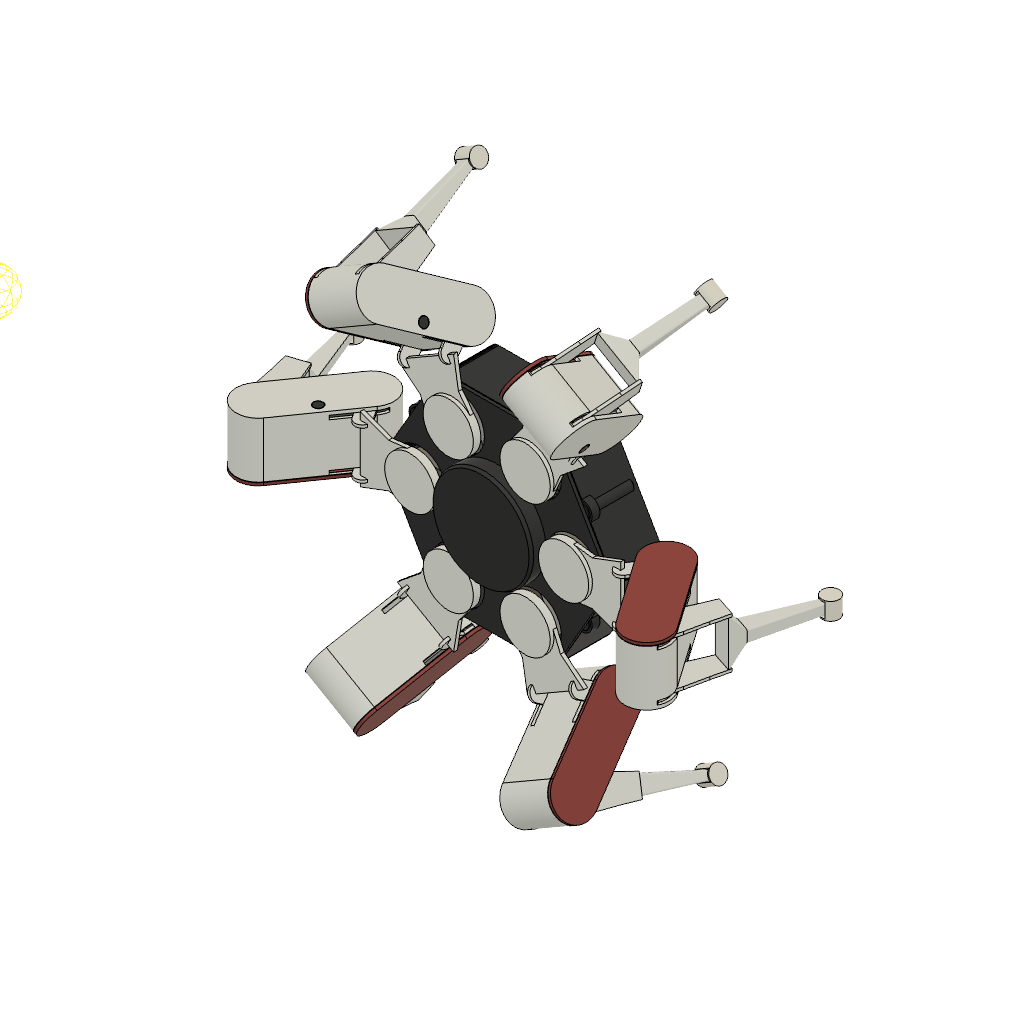
final-concept (Autodesk Fusion 360 design; units mm, degrees)
part number: 2026-10-13-02-30-10-488
part number: 2026-10-13-02-30-11-030
part number: 2026-10-13-02-30-12-968
part number: 2026-10-13-02-30-14-273
part number: 2026-10-13-02-30-15-877
part number: 2026-10-13-02-30-17-179
part number: 2026-10-13-02-30-18-648
part number: 2026-10-13-02-30-19-201
part number: 2026-10-13-02-30-20-901
part number: 2026-10-13-02-30-21-364
part number: 2026-10-13-02-30-21-593
part number: 2026-10-13-02-30-21-831
part number: 2026-10-13-02-30-33-109
part number: 2026-10-13-02-30-33-523
part number: 2026-10-13-02-30-34-018
part number: 2026-10-13-02-30-34-370
part number: 2026-10-13-02-30-34-939
part number: 2026-10-13-02-30-35-478
part number: 2026-10-13-02-30-36-031
part number: 2026-10-13-02-30-36-586
part number: 2026-10-13-02-30-37-150
part number: 2026-10-13-02-30-37-730
part number: 2026-10-13-02-30-38-365
part number: 2026-10-13-02-30-39-006
part number: 2026-10-13-02-30-39-649
part number: 2026-10-13-02-30-40-309
part number: 2026-10-13-02-30-40-984
Autodesk Fusion 360 part; units mm, degrees
(part 1 of 3)
ref_plane "WorkPlane1" through (0, 0, -32) normal (0, 0, 1) x (1, 0, 0) in component "CORE | CoreTub"
sketch "Continuous structural body" plane through (0, 0, -32) normal (0, 0, 1) x (1, 0, 0) in component "CORE | CoreTub"
  line L0 (71.1962, -3) -> (71.5433, -2.2961)
  line L1 (71.5433, -2.2961) -> (71.7956, -1.5529)
  line L2 (71.7956, -1.5529) -> (71.9487, -0.7832)
  line L3 (71.9487, -0.7832) -> (72, 0)
  line L4 (72, 0) -> (71.9487, 0.7832)
  line L5 (71.9487, 0.7832) -> (71.7956, 1.5529)
  line L6 (71.7956, 1.5529) -> (71.5433, 2.2961)
  line L7 (71.5433, 2.2961) -> (71.1962, 3)
  line L8 (71.1962, 3) -> (38.1962, 60.1577)
  line L9 (38.1962, 60.1577) -> (37.7601, 60.8102)
  line L10 (37.7601, 60.8102) -> (37.2426, 61.4003)
  line L11 (37.2426, 61.4003) -> (36.6526, 61.9178)
  line L12 (36.6526, 61.9178) -> (36, 62.3538)
  line L13 (36, 62.3538) -> (35.2961, 62.701)
  line L14 (35.2961, 62.701) -> (34.5529, 62.9532)
  line L15 (34.5529, 62.9532) -> (33.7832, 63.1063)
  line L16 (33.7832, 63.1063) -> (33, 63.1577)
  line L17 (33, 63.1577) -> (-33, 63.1577)
  line L18 (-33, 63.1577) -> (-33.7832, 63.1063)
  line L19 (-33.7832, 63.1063) -> (-34.5529, 62.9532)
  line L20 (-34.5529, 62.9532) -> (-35.2961, 62.701)
  line L21 (-35.2961, 62.701) -> (-36, 62.3538)
  line L22 (-36, 62.3538) -> (-36.6526, 61.9178)
  line L23 (-36.6526, 61.9178) -> (-37.2426, 61.4003)
  line L24 (-37.2426, 61.4003) -> (-37.7601, 60.8102)
  line L25 (-37.7601, 60.8102) -> (-38.1962, 60.1577)
  line L26 (-38.1962, 60.1577) -> (-71.1962, 3)
  line L27 (-71.1962, 3) -> (-71.5433, 2.2961)
  line L28 (-71.5433, 2.2961) -> (-71.7956, 1.5529)
  line L29 (-71.7956, 1.5529) -> (-71.9487, 0.7832)
  line L30 (-71.9487, 0.7832) -> (-72, 0)
  line L31 (-72, 0) -> (-71.9487, -0.7832)
  line L32 (-71.9487, -0.7832) -> (-71.7956, -1.5529)
  line L33 (-71.7956, -1.5529) -> (-71.5433, -2.2961)
  line L34 (-71.5433, -2.2961) -> (-71.1962, -3)
  line L35 (-71.1962, -3) -> (-38.1962, -60.1577)
  line L36 (-38.1962, -60.1577) -> (-37.7601, -60.8102)
  line L37 (-37.7601, -60.8102) -> (-37.2426, -61.4003)
  line L38 (-37.2426, -61.4003) -> (-36.6526, -61.9178)
  line L39 (-36.6526, -61.9178) -> (-36, -62.3538)
  line L40 (-36, -62.3538) -> (-35.2961, -62.701)
  line L41 (-35.2961, -62.701) -> (-34.5529, -62.9532)
  line L42 (-34.5529, -62.9532) -> (-33.7832, -63.1063)
  line L43 (-33.7832, -63.1063) -> (-33, -63.1577)
  line L44 (-33, -63.1577) -> (33, -63.1577)
  line L45 (33, -63.1577) -> (33.7832, -63.1063)
  line L46 (33.7832, -63.1063) -> (34.5529, -62.9532)
  line L47 (34.5529, -62.9532) -> (35.2961, -62.701)
  line L48 (35.2961, -62.701) -> (36, -62.3538)
  line L49 (36, -62.3538) -> (36.6526, -61.9178)
  line L50 (36.6526, -61.9178) -> (37.2426, -61.4003)
  line L51 (37.2426, -61.4003) -> (37.7601, -60.8102)
  line L52 (37.7601, -60.8102) -> (38.1962, -60.1577)
  line L53 (38.1962, -60.1577) -> (71.1962, -3)
extrude "Continuous structural body (1)" add sketch "Continuous structural body" along normal blind 32 makes body 1 in component "CORE | CoreTub"
ref_plane "WorkPlane2" through (0, 0, -29) normal (0, 0, 1) x (1, 0, 0) in component "CORE | CoreTub"
sketch "Hollow core with 3mm floor and 1.8mm walls" plane through (0, 0, -29) normal (0, 0, 1) x (1, 0, 0) in component "CORE | CoreTub"
  line L0 (69.6373, -2.1) -> (69.8803, -1.6073)
  line L1 (69.8803, -1.6073) -> (70.0569, -1.087)
  line L2 (70.0569, -1.087) -> (70.1641, -0.5482)
  line L3 (70.1641, -0.5482) -> (70.2, 0)
  line L4 (70.2, 0) -> (70.1641, 0.5482)
  line L5 (70.1641, 0.5482) -> (70.0569, 1.087)
  line L6 (70.0569, 1.087) -> (69.8803, 1.6073)
  line L7 (69.8803, 1.6073) -> (69.6373, 2.1)
  line L8 (69.6373, 2.1) -> (36.6373, 59.2577)
  line L9 (36.6373, 59.2577) -> (36.3321, 59.7145)
  line L10 (36.3321, 59.7145) -> (35.9698, 60.1275)
  line L11 (35.9698, 60.1275) -> (35.5568, 60.4898)
  line L12 (35.5568, 60.4898) -> (35.1, 60.795)
  line L13 (35.1, 60.795) -> (34.6073, 61.038)
  line L14 (34.6073, 61.038) -> (34.087, 61.2146)
  line L15 (34.087, 61.2146) -> (33.5482, 61.3217)
  line L16 (33.5482, 61.3217) -> (33, 61.3577)
  line L17 (33, 61.3577) -> (-33, 61.3577)
  line L18 (-33, 61.3577) -> (-33.5482, 61.3217)
  line L19 (-33.5482, 61.3217) -> (-34.087, 61.2146)
  line L20 (-34.087, 61.2146) -> (-34.6073, 61.038)
  line L21 (-34.6073, 61.038) -> (-35.1, 60.795)
  line L22 (-35.1, 60.795) -> (-35.5568, 60.4898)
  line L23 (-35.5568, 60.4898) -> (-35.9698, 60.1275)
  line L24 (-35.9698, 60.1275) -> (-36.3321, 59.7145)
  line L25 (-36.3321, 59.7145) -> (-36.6373, 59.2577)
  line L26 (-36.6373, 59.2577) -> (-69.6373, 2.1)
  line L27 (-69.6373, 2.1) -> (-69.8803, 1.6073)
  line L28 (-69.8803, 1.6073) -> (-70.0569, 1.087)
  line L29 (-70.0569, 1.087) -> (-70.1641, 0.5482)
  line L30 (-70.1641, 0.5482) -> (-70.2, 0)
  line L31 (-70.2, 0) -> (-70.1641, -0.5482)
  line L32 (-70.1641, -0.5482) -> (-70.0569, -1.087)
  line L33 (-70.0569, -1.087) -> (-69.8803, -1.6073)
  line L34 (-69.8803, -1.6073) -> (-69.6373, -2.1)
  line L35 (-69.6373, -2.1) -> (-36.6373, -59.2577)
  line L36 (-36.6373, -59.2577) -> (-36.3321, -59.7145)
  line L37 (-36.3321, -59.7145) -> (-35.9698, -60.1275)
  line L38 (-35.9698, -60.1275) -> (-35.5568, -60.4898)
  line L39 (-35.5568, -60.4898) -> (-35.1, -60.795)
  line L40 (-35.1, -60.795) -> (-34.6073, -61.038)
  line L41 (-34.6073, -61.038) -> (-34.087, -61.2146)
  line L42 (-34.087, -61.2146) -> (-33.5482, -61.3217)
  line L43 (-33.5482, -61.3217) -> (-33, -61.3577)
  line L44 (-33, -61.3577) -> (33, -61.3577)
  line L45 (33, -61.3577) -> (33.5482, -61.3217)
  line L46 (33.5482, -61.3217) -> (34.087, -61.2146)
  line L47 (34.087, -61.2146) -> (34.6073, -61.038)
  line L48 (34.6073, -61.038) -> (35.1, -60.795)
  line L49 (35.1, -60.795) -> (35.5568, -60.4898)
  line L50 (35.5568, -60.4898) -> (35.9698, -60.1275)
  line L51 (35.9698, -60.1275) -> (36.3321, -59.7145)
  line L52 (36.3321, -59.7145) -> (36.6373, -59.2577)
  line L53 (36.6373, -59.2577) -> (69.6373, -2.1)
extrude "Hollow core with 3mm floor and 1.8mm walls (1)" cut sketch "Hollow core with 3mm floor and 1.8mm walls" along normal blind 29 bodies 1 in component "CORE | CoreTub"
ref_plane "WorkPlane3" through (0, 0, -29) normal (0, 0, 1) x (1, 0, 0) in component "CORE | CoreTub"
sketch "Integral concealed lid screw column" plane through (0, 0, -29) normal (0, 0, 1) x (1, 0, 0) in component "CORE | CoreTub"
  circle A0 centre (51.9615, 30) radius 4.2
extrude "Integral concealed lid screw column (1)" add sketch "Integral concealed lid screw column" along normal blind 29 bodies 1 in component "CORE | CoreTub"
ref_plane "WorkPlane4" through (0, 0, -32) normal (0, 0, 1) x (1, 0, 0) in component "CORE | CoreTub"
sketch "Underside M3 clearance shaft" plane through (0, 0, -32) normal (0, 0, 1) x (1, 0, 0) in component "CORE | CoreTub"
  circle A0 centre (51.9615, 30) radius 1.7
extrude "Underside M3 clearance shaft (1)" cut sketch "Underside M3 clearance shaft" along normal blind 32 bodies 1 in component "CORE | CoreTub"
ref_plane "WorkPlane5" through (0, 0, -32) normal (0, 0, 1) x (1, 0, 0) in component "CORE | CoreTub"
sketch "Recessed underside screw head" plane through (0, 0, -32) normal (0, 0, 1) x (1, 0, 0) in component "CORE | CoreTub"
  circle A0 centre (51.9615, 30) radius 3.1
extrude "Recessed underside screw head (1)" cut sketch "Recessed underside screw head" along normal blind 2 bodies 1 in component "CORE | CoreTub"
ref_plane "WorkPlane6" through (0, 0, -5) normal (0, 0, 1) x (1, 0, 0) in component "CORE | CoreTub"
sketch "Integral wide insert seating collar" plane through (0, 0, -5) normal (0, 0, 1) x (1, 0, 0) in component "CORE | CoreTub"
  circle A0 centre (51.9615, 30) radius 6.5
extrude "Integral wide insert seating collar (1)" add sketch "Integral wide insert seating collar" along normal blind 5 bodies 1 in component "CORE | CoreTub"
ref_plane "WorkPlane7" through (0, 0, -5) normal (0, 0, 1) x (1, 0, 0) in component "CORE | CoreTub"
sketch "Keep screw shaft open through widened collar" plane through (0, 0, -5) normal (0, 0, 1) x (1, 0, 0) in component "CORE | CoreTub"
  circle A0 centre (51.9615, 30) radius 1.7
extrude "Keep screw shaft open through widened collar (1)" cut sketch "Keep screw shaft open through widened collar" along normal blind 5 bodies 1 in component "CORE | CoreTub"
ref_plane "WorkPlane8" through (0, 0, -4) normal (0, 0, 1) x (1, 0, 0) in component "CORE | CoreTub"
sketch "Lid boss receiving pocket with radial clearance" plane through (0, 0, -4) normal (0, 0, 1) x (1, 0, 0) in component "CORE | CoreTub"
  circle A0 centre (51.9615, 30) radius 5.3
extrude "Lid boss receiving pocket with radial clearance (1)" cut sketch "Lid boss receiving pocket with radial clearance" along normal blind 4 bodies 1 in component "CORE | CoreTub"
ref_plane "WorkPlane9" through (0, 0, -29) normal (0, 0, 1) x (1, 0, 0) in component "CORE | CoreTub"
sketch "Integral concealed lid screw column (1)" plane through (0, 0, -29) normal (0, 0, 1) x (1, 0, 0) in component "CORE | CoreTub"
  circle A0 centre (-51.9615, 30) radius 4.2
extrude "Integral concealed lid screw column (2)" add sketch "Integral concealed lid screw column (1)" along normal blind 29 bodies 1 in component "CORE | CoreTub"
ref_plane "WorkPlane10" through (0, 0, -32) normal (0, 0, 1) x (1, 0, 0) in component "CORE | CoreTub"
sketch "Underside M3 clearance shaft (1)" plane through (0, 0, -32) normal (0, 0, 1) x (1, 0, 0) in component "CORE | CoreTub"
  circle A0 centre (-51.9615, 30) radius 1.7
extrude "Underside M3 clearance shaft (2)" cut sketch "Underside M3 clearance shaft (1)" along normal blind 32 bodies 1 in component "CORE | CoreTub"
ref_plane "WorkPlane11" through (0, 0, -32) normal (0, 0, 1) x (1, 0, 0) in component "CORE | CoreTub"
sketch "Recessed underside screw head (1)" plane through (0, 0, -32) normal (0, 0, 1) x (1, 0, 0) in component "CORE | CoreTub"
  circle A0 centre (-51.9615, 30) radius 3.1
extrude "Recessed underside screw head (2)" cut sketch "Recessed underside screw head (1)" along normal blind 2 bodies 1 in component "CORE | CoreTub"
ref_plane "WorkPlane12" through (0, 0, -5) normal (0, 0, 1) x (1, 0, 0) in component "CORE | CoreTub"
sketch "Integral wide insert seating collar (1)" plane through (0, 0, -5) normal (0, 0, 1) x (1, 0, 0) in component "CORE | CoreTub"
  circle A0 centre (-51.9615, 30) radius 6.5
extrude "Integral wide insert seating collar (2)" add sketch "Integral wide insert seating collar (1)" along normal blind 5 bodies 1 in component "CORE | CoreTub"
ref_plane "WorkPlane13" through (0, 0, -5) normal (0, 0, 1) x (1, 0, 0) in component "CORE | CoreTub"
sketch "Keep screw shaft open through widened collar (1)" plane through (0, 0, -5) normal (0, 0, 1) x (1, 0, 0) in component "CORE | CoreTub"
  circle A0 centre (-51.9615, 30) radius 1.7
extrude "Keep screw shaft open through widened collar (2)" cut sketch "Keep screw shaft open through widened collar (1)" along normal blind 5 bodies 1 in component "CORE | CoreTub"
ref_plane "WorkPlane14" through (0, 0, -4) normal (0, 0, 1) x (1, 0, 0) in component "CORE | CoreTub"
sketch "Lid boss receiving pocket with radial clearance (1)" plane through (0, 0, -4) normal (0, 0, 1) x (1, 0, 0) in component "CORE | CoreTub"
  circle A0 centre (-51.9615, 30) radius 5.3
extrude "Lid boss receiving pocket with radial clearance (2)" cut sketch "Lid boss receiving pocket with radial clearance (1)" along normal blind 4 bodies 1 in component "CORE | CoreTub"
ref_plane "WorkPlane15" through (0, 0, -29) normal (0, 0, 1) x (1, 0, 0) in component "CORE | CoreTub"
sketch "Integral concealed lid screw column (2)" plane through (0, 0, -29) normal (0, 0, 1) x (1, 0, 0) in component "CORE | CoreTub"
  circle A0 centre (-51.9615, -30) radius 4.2
extrude "Integral concealed lid screw column (3)" add sketch "Integral concealed lid screw column (2)" along normal blind 29 bodies 1 in component "CORE | CoreTub"
ref_plane "WorkPlane16" through (0, 0, -32) normal (0, 0, 1) x (1, 0, 0) in component "CORE | CoreTub"
sketch "Underside M3 clearance shaft (2)" plane through (0, 0, -32) normal (0, 0, 1) x (1, 0, 0) in component "CORE | CoreTub"
  circle A0 centre (-51.9615, -30) radius 1.7
extrude "Underside M3 clearance shaft (3)" cut sketch "Underside M3 clearance shaft (2)" along normal blind 32 bodies 1 in component "CORE | CoreTub"
ref_plane "WorkPlane17" through (0, 0, -32) normal (0, 0, 1) x (1, 0, 0) in component "CORE | CoreTub"
sketch "Recessed underside screw head (2)" plane through (0, 0, -32) normal (0, 0, 1) x (1, 0, 0) in component "CORE | CoreTub"
  circle A0 centre (-51.9615, -30) radius 3.1
extrude "Recessed underside screw head (3)" cut sketch "Recessed underside screw head (2)" along normal blind 2 bodies 1 in component "CORE | CoreTub"
ref_plane "WorkPlane18" through (0, 0, -5) normal (0, 0, 1) x (1, 0, 0) in component "CORE | CoreTub"
sketch "Integral wide insert seating collar (2)" plane through (0, 0, -5) normal (0, 0, 1) x (1, 0, 0) in component "CORE | CoreTub"
  circle A0 centre (-51.9615, -30) radius 6.5
extrude "Integral wide insert seating collar (3)" add sketch "Integral wide insert seating collar (2)" along normal blind 5 bodies 1 in component "CORE | CoreTub"
ref_plane "WorkPlane19" through (0, 0, -5) normal (0, 0, 1) x (1, 0, 0) in component "CORE | CoreTub"
sketch "Keep screw shaft open through widened collar (2)" plane through (0, 0, -5) normal (0, 0, 1) x (1, 0, 0) in component "CORE | CoreTub"
  circle A0 centre (-51.9615, -30) radius 1.7
extrude "Keep screw shaft open through widened collar (3)" cut sketch "Keep screw shaft open through widened collar (2)" along normal blind 5 bodies 1 in component "CORE | CoreTub"
ref_plane "WorkPlane20" through (0, 0, -4) normal (0, 0, 1) x (1, 0, 0) in component "CORE | CoreTub"
sketch "Lid boss receiving pocket with radial clearance (2)" plane through (0, 0, -4) normal (0, 0, 1) x (1, 0, 0) in component "CORE | CoreTub"
  circle A0 centre (-51.9615, -30) radius 5.3
extrude "Lid boss receiving pocket with radial clearance (3)" cut sketch "Lid boss receiving pocket with radial clearance (2)" along normal blind 4 bodies 1 in component "CORE | CoreTub"
ref_plane "WorkPlane21" through (0, 0, -29) normal (0, 0, 1) x (1, 0, 0) in component "CORE | CoreTub"
sketch "Integral concealed lid screw column (3)" plane through (0, 0, -29) normal (0, 0, 1) x (1, 0, 0) in component "CORE | CoreTub"
  circle A0 centre (51.9615, -30) radius 4.2
extrude "Integral concealed lid screw column (4)" add sketch "Integral concealed lid screw column (3)" along normal blind 29 bodies 1 in component "CORE | CoreTub"
ref_plane "WorkPlane22" through (0, 0, -32) normal (0, 0, 1) x (1, 0, 0) in component "CORE | CoreTub"
sketch "Underside M3 clearance shaft (3)" plane through (0, 0, -32) normal (0, 0, 1) x (1, 0, 0) in component "CORE | CoreTub"
  circle A0 centre (51.9615, -30) radius 1.7
extrude "Underside M3 clearance shaft (4)" cut sketch "Underside M3 clearance shaft (3)" along normal blind 32 bodies 1 in component "CORE | CoreTub"
ref_plane "WorkPlane23" through (0, 0, -32) normal (0, 0, 1) x (1, 0, 0) in component "CORE | CoreTub"
sketch "Recessed underside screw head (3)" plane through (0, 0, -32) normal (0, 0, 1) x (1, 0, 0) in component "CORE | CoreTub"
  circle A0 centre (51.9615, -30) radius 3.1
extrude "Recessed underside screw head (4)" cut sketch "Recessed underside screw head (3)" along normal blind 2 bodies 1 in component "CORE | CoreTub"
ref_plane "WorkPlane24" through (0, 0, -5) normal (0, 0, 1) x (1, 0, 0) in component "CORE | CoreTub"
sketch "Integral wide insert seating collar (3)" plane through (0, 0, -5) normal (0, 0, 1) x (1, 0, 0) in component "CORE | CoreTub"
  circle A0 centre (51.9615, -30) radius 6.5
extrude "Integral wide insert seating collar (4)" add sketch "Integral wide insert seating collar (3)" along normal blind 5 bodies 1 in component "CORE | CoreTub"
ref_plane "WorkPlane25" through (0, 0, -5) normal (0, 0, 1) x (1, 0, 0) in component "CORE | CoreTub"
sketch "Keep screw shaft open through widened collar (3)" plane through (0, 0, -5) normal (0, 0, 1) x (1, 0, 0) in component "CORE | CoreTub"
  circle A0 centre (51.9615, -30) radius 1.7
extrude "Keep screw shaft open through widened collar (4)" cut sketch "Keep screw shaft open through widened collar (3)" along normal blind 5 bodies 1 in component "CORE | CoreTub"
ref_plane "WorkPlane26" through (0, 0, -4) normal (0, 0, 1) x (1, 0, 0) in component "CORE | CoreTub"
sketch "Lid boss receiving pocket with radial clearance (3)" plane through (0, 0, -4) normal (0, 0, 1) x (1, 0, 0) in component "CORE | CoreTub"
  circle A0 centre (51.9615, -30) radius 5.3
extrude "Lid boss receiving pocket with radial clearance (4)" cut sketch "Lid boss receiving pocket with radial clearance (3)" along normal blind 4 bodies 1 in component "CORE | CoreTub"
ref_plane "WorkPlane27" through (0, 0, -29) normal (0, 0, 1) x (1, 0, 0) in component "CORE | CoreTub"
sketch "Integral cassette support column" plane through (0, 0, -29) normal (0, 0, 1) x (1, 0, 0) in component "CORE | CoreTub"
  circle A0 centre (21, 16) radius 3.5
extrude "Integral cassette support column (1)" add sketch "Integral cassette support column" along normal blind 14 bodies 1 in component "CORE | CoreTub"
ref_plane "WorkPlane28" through (0, 0, -20) normal (0, 0, 1) x (1, 0, 0) in component "CORE | CoreTub"
sketch "Provisional M3 insert cavity, cassette" plane through (0, 0, -20) normal (0, 0, 1) x (1, 0, 0) in component "CORE | CoreTub"
  circle A0 centre (21, 16) radius 2.1
extrude "Provisional M3 insert cavity, cassette (1)" cut sketch "Provisional M3 insert cavity, cassette" along normal blind 5 bodies 1 in component "CORE | CoreTub"
ref_plane "WorkPlane29" through (0, 0, -29) normal (0, 0, 1) x (1, 0, 0) in component "CORE | CoreTub"
sketch "Integral cassette support column (1)" plane through (0, 0, -29) normal (0, 0, 1) x (1, 0, 0) in component "CORE | CoreTub"
  circle A0 centre (-21, -16) radius 3.5
extrude "Integral cassette support column (2)" add sketch "Integral cassette support column (1)" along normal blind 14 bodies 1 in component "CORE | CoreTub"
ref_plane "WorkPlane30" through (0, 0, -20) normal (0, 0, 1) x (1, 0, 0) in component "CORE | CoreTub"
sketch "Provisional M3 insert cavity, cassette (1)" plane through (0, 0, -20) normal (0, 0, 1) x (1, 0, 0) in component "CORE | CoreTub"
  circle A0 centre (-21, -16) radius 2.1
extrude "Provisional M3 insert cavity, cassette (2)" cut sketch "Provisional M3 insert cavity, cassette (1)" along normal blind 5 bodies 1 in component "CORE | CoreTub"
ref_plane "WorkPlane31" through (0, 0, -29) normal (0, 0, 1) x (1, 0, 0) in component "CORE | CoreTub"
sketch "Battery side guide, foam allowance" plane through (0, 0, -29) normal (0, 0, 1) x (1, 0, 0) in component "CORE | CoreTub"
  line L0 (-24, -9) -> (-22.6, -9)
  line L1 (-22.6, -9) -> (-22.6, 9)
  line L2 (-22.6, 9) -> (-24, 9)
  line L3 (-24, 9) -> (-24, -9)
extrude "Battery side guide, foam allowance (1)" add sketch "Battery side guide, foam allowance" along normal blind 2 bodies 1 in component "CORE | CoreTub"
ref_plane "WorkPlane32" through (0, 0, -29) normal (0, 0, 1) x (1, 0, 0) in component "CORE | CoreTub"
sketch "Battery side guide, foam allowance (1)" plane through (0, 0, -29) normal (0, 0, 1) x (1, 0, 0) in component "CORE | CoreTub"
  line L0 (22.6, -9) -> (24, -9)
  line L1 (24, -9) -> (24, 9)
  line L2 (24, 9) -> (22.6, 9)
  line L3 (22.6, 9) -> (22.6, -9)
extrude "Battery side guide, foam allowance (2)" add sketch "Battery side guide, foam allowance (1)" along normal blind 2 bodies 1 in component "CORE | CoreTub"
ref_plane "WorkPlane33" through (0, 0, -29) normal (0, 0, 1) x (1, 0, 0) in component "CORE | CoreTub"
sketch "Battery end guide" plane through (0, 0, -29) normal (0, 0, 1) x (1, 0, 0) in component "CORE | CoreTub"
  line L0 (-21.8, -13.7) -> (21.8, -13.7)
  line L1 (21.8, -13.7) -> (21.8, -12.3)
  line L2 (21.8, -12.3) -> (-21.8, -12.3)
  line L3 (-21.8, -12.3) -> (-21.8, -13.7)
extrude "Battery end guide (1)" add sketch "Battery end guide" along normal blind 2 bodies 1 in component "CORE | CoreTub"
ref_plane "WorkPlane34" through (0, 0, -29) normal (0, 0, 1) x (1, 0, 0) in component "CORE | CoreTub"
sketch "Battery end guide (1)" plane through (0, 0, -29) normal (0, 0, 1) x (1, 0, 0) in component "CORE | CoreTub"
  line L0 (-21.8, 12.3) -> (21.8, 12.3)
  line L1 (21.8, 12.3) -> (21.8, 13.7)
  line L2 (21.8, 13.7) -> (-21.8, 13.7)
  line L3 (-21.8, 13.7) -> (-21.8, 12.3)
extrude "Battery end guide (2)" add sketch "Battery end guide (1)" along normal blind 2 bodies 1 in component "CORE | CoreTub"
ref_plane "WorkPlane35" through (0, 0, -32) normal (0, 0, 1) x (1, 0, 0) in component "CORE | CoreTub"
sketch "Battery soft strap routing" plane through (0, 0, -32) normal (0, 0, 1) x (1, 0, 0) in component "CORE | CoreTub"
  line L0 (-25.3, -8) -> (-25.3, 8)
  arc A0 (-22.7, 8) -> (-25.3, 8) centre (-24, 8) ccw
  line L1 (-22.7, 8) -> (-22.7, -8)
  arc A1 (-25.3, -8) -> (-22.7, -8) centre (-24, -8) ccw
  line L2 (22.7, -8) -> (22.7, 8)
  arc A2 (25.3, 8) -> (22.7, 8) centre (24, 8) ccw
  line L3 (25.3, 8) -> (25.3, -8)
  arc A3 (22.7, -8) -> (25.3, -8) centre (24, -8) ccw
extrude "Battery soft strap routing (1)" cut sketch "Battery soft strap routing" along normal blind 3 bodies 1 in component "CORE | CoreTub"
ref_plane "WorkPlane36" through (0, 0, -32) normal (0, 0, 1) x (1, 0, 0) in component "CORE | CoreTub"
sketch "Discreet underside ventilation slot" plane through (0, 0, -32) normal (0, 0, 1) x (1, 0, 0) in component "CORE | CoreTub"
  line L0 (29.7609, 18.4526) -> (36.6891, 22.4526)
  arc A0 (37.7891, 20.5474) -> (36.6891, 22.4526) centre (37.2391, 21.5) ccw
  line L1 (37.7891, 20.5474) -> (30.8609, 16.5474)
  arc A1 (29.7609, 18.4526) -> (30.8609, 16.5474) centre (30.3109, 17.5) ccw
extrude "Discreet underside ventilation slot (1)" cut sketch "Discreet underside ventilation slot" along normal blind 3 bodies 1 in component "CORE | CoreTub"
ref_plane "WorkPlane37" through (0, 0, -32) normal (0, 0, 1) x (1, 0, 0) in component "CORE | CoreTub"
sketch "Discreet underside ventilation slot (1)" plane through (0, 0, -32) normal (0, 0, 1) x (1, 0, 0) in component "CORE | CoreTub"
  line L0 (-1.1, 35) -> (-1.1, 43)
  arc A0 (1.1, 43) -> (-1.1, 43) centre (0, 43) ccw
  line L1 (1.1, 43) -> (1.1, 35)
  arc A1 (-1.1, 35) -> (1.1, 35) centre (0, 35) ccw
extrude "Discreet underside ventilation slot (2)" cut sketch "Discreet underside ventilation slot (1)" along normal blind 3 bodies 1 in component "CORE | CoreTub"
ref_plane "WorkPlane38" through (0, 0, -32) normal (0, 0, 1) x (1, 0, 0) in component "CORE | CoreTub"
sketch "Discreet underside ventilation slot (2)" plane through (0, 0, -32) normal (0, 0, 1) x (1, 0, 0) in component "CORE | CoreTub"
  line L0 (-30.8609, 16.5474) -> (-37.7891, 20.5474)
  arc A0 (-36.6891, 22.4526) -> (-37.7891, 20.5474) centre (-37.2391, 21.5) ccw
  line L1 (-36.6891, 22.4526) -> (-29.7609, 18.4526)
  arc A1 (-30.8609, 16.5474) -> (-29.7609, 18.4526) centre (-30.3109, 17.5) ccw
extrude "Discreet underside ventilation slot (3)" cut sketch "Discreet underside ventilation slot (2)" along normal blind 3 bodies 1 in component "CORE | CoreTub"
ref_plane "WorkPlane39" through (0, 0, -32) normal (0, 0, 1) x (1, 0, 0) in component "CORE | CoreTub"
sketch "Discreet underside ventilation slot (3)" plane through (0, 0, -32) normal (0, 0, 1) x (1, 0, 0) in component "CORE | CoreTub"
  line L0 (-29.7609, -18.4526) -> (-36.6891, -22.4526)
  arc A0 (-37.7891, -20.5474) -> (-36.6891, -22.4526) centre (-37.2391, -21.5) ccw
  line L1 (-37.7891, -20.5474) -> (-30.8609, -16.5474)
  arc A1 (-29.7609, -18.4526) -> (-30.8609, -16.5474) centre (-30.3109, -17.5) ccw
extrude "Discreet underside ventilation slot (4)" cut sketch "Discreet underside ventilation slot (3)" along normal blind 3 bodies 1 in component "CORE | CoreTub"
ref_plane "WorkPlane40" through (0, 0, -32) normal (0, 0, 1) x (1, 0, 0) in component "CORE | CoreTub"
sketch "Discreet underside ventilation slot (4)" plane through (0, 0, -32) normal (0, 0, 1) x (1, 0, 0) in component "CORE | CoreTub"
  line L0 (1.1, -35) -> (1.1, -43)
  arc A0 (-1.1, -43) -> (1.1, -43) centre (0, -43) ccw
  line L1 (-1.1, -43) -> (-1.1, -35)
  arc A1 (1.1, -35) -> (-1.1, -35) centre (0, -35) ccw
extrude "Discreet underside ventilation slot (5)" cut sketch "Discreet underside ventilation slot (4)" along normal blind 3 bodies 1 in component "CORE | CoreTub"
ref_plane "WorkPlane41" through (0, 0, -32) normal (0, 0, 1) x (1, 0, 0) in component "CORE | CoreTub"
sketch "Discreet underside ventilation slot (5)" plane through (0, 0, -32) normal (0, 0, 1) x (1, 0, 0) in component "CORE | CoreTub"
  line L0 (30.8609, -16.5474) -> (37.7891, -20.5474)
  arc A0 (36.6891, -22.4526) -> (37.7891, -20.5474) centre (37.2391, -21.5) ccw
  line L1 (36.6891, -22.4526) -> (29.7609, -18.4526)
  arc A1 (30.8609, -16.5474) -> (29.7609, -18.4526) centre (30.3109, -17.5) ccw
extrude "Discreet underside ventilation slot (6)" cut sketch "Discreet underside ventilation slot (5)" along normal blind 3 bodies 1 in component "CORE | CoreTub"
ref_plane "WorkPlane42" through (0, 0, -32) normal (0, 0, 1) x (1, 0, 0) in component "CORE | CoreTub"
sketch "Underside weight relief between actuator bays" plane through (0, 0, -32) normal (0, 0, 1) x (1, 0, 0) in component "CORE | CoreTub"
  line L0 (29.4808, 8.9378) -> (50.8993, 17.8397)
  line L1 (50.8993, 17.8397) -> (50.2295, 29)
  line L2 (50.2295, 29) -> (40.8993, 35.1603)
  line L3 (40.8993, 35.1603) -> (22.4808, 21.0622)
  line L4 (22.4808, 21.0622) -> (29.4808, 8.9378)
extrude "Underside weight relief between actuator bays (1)" cut sketch "Underside weight relief between actuator bays" along normal blind 3 bodies 1 in component "CORE | CoreTub"
ref_plane "WorkPlane43" through (0, 0, -32) normal (0, 0, 1) x (1, 0, 0) in component "CORE | CoreTub"
sketch "Underside weight relief between actuator bays (1)" plane through (0, 0, -32) normal (0, 0, 1) x (1, 0, 0) in component "CORE | CoreTub"
  line L0 (7, 30) -> (10, 53)
  line L1 (10, 53) -> (0, 58)
  line L2 (0, 58) -> (-10, 53)
  line L3 (-10, 53) -> (-7, 30)
  line L4 (-7, 30) -> (7, 30)
extrude "Underside weight relief between actuator bays (2)" cut sketch "Underside weight relief between actuator bays (1)" along normal blind 3 bodies 1 in component "CORE | CoreTub"
ref_plane "WorkPlane44" through (0, 0, -32) normal (0, 0, 1) x (1, 0, 0) in component "CORE | CoreTub"
sketch "Underside weight relief between actuator bays (2)" plane through (0, 0, -32) normal (0, 0, 1) x (1, 0, 0) in component "CORE | CoreTub"
  line L0 (-22.4808, 21.0622) -> (-40.8993, 35.1603)
  line L1 (-40.8993, 35.1603) -> (-50.2295, 29)
  line L2 (-50.2295, 29) -> (-50.8993, 17.8397)
  line L3 (-50.8993, 17.8397) -> (-29.4808, 8.9378)
  line L4 (-29.4808, 8.9378) -> (-22.4808, 21.0622)
extrude "Underside weight relief between actuator bays (3)" cut sketch "Underside weight relief between actuator bays (2)" along normal blind 3 bodies 1 in component "CORE | CoreTub"
ref_plane "WorkPlane45" through (0, 0, -32) normal (0, 0, 1) x (1, 0, 0) in component "CORE | CoreTub"
sketch "Underside weight relief between actuator bays (3)" plane through (0, 0, -32) normal (0, 0, 1) x (1, 0, 0) in component "CORE | CoreTub"
  line L0 (-29.4808, -8.9378) -> (-50.8993, -17.8397)
  line L1 (-50.8993, -17.8397) -> (-50.2295, -29)
  line L2 (-50.2295, -29) -> (-40.8993, -35.1603)
  line L3 (-40.8993, -35.1603) -> (-22.4808, -21.0622)
  line L4 (-22.4808, -21.0622) -> (-29.4808, -8.9378)
extrude "Underside weight relief between actuator bays (4)" cut sketch "Underside weight relief between actuator bays (3)" along normal blind 3 bodies 1 in component "CORE | CoreTub"
ref_plane "WorkPlane46" through (0, 0, -32) normal (0, 0, 1) x (1, 0, 0) in component "CORE | CoreTub"
sketch "Underside weight relief between actuator bays (4)" plane through (0, 0, -32) normal (0, 0, 1) x (1, 0, 0) in component "CORE | CoreTub"
  line L0 (-7, -30) -> (-10, -53)
  line L1 (-10, -53) -> (0, -58)
  line L2 (0, -58) -> (10, -53)
  line L3 (10, -53) -> (7, -30)
  line L4 (7, -30) -> (-7, -30)
extrude "Underside weight relief between actuator bays (5)" cut sketch "Underside weight relief between actuator bays (4)" along normal blind 3 bodies 1 in component "CORE | CoreTub"
ref_plane "WorkPlane47" through (0, 0, -32) normal (0, 0, 1) x (1, 0, 0) in component "CORE | CoreTub"
sketch "Underside weight relief between actuator bays (5)" plane through (0, 0, -32) normal (0, 0, 1) x (1, 0, 0) in component "CORE | CoreTub"
  line L0 (22.4808, -21.0622) -> (40.8993, -35.1603)
  line L1 (40.8993, -35.1603) -> (50.2295, -29)
  line L2 (50.2295, -29) -> (50.8993, -17.8397)
  line L3 (50.8993, -17.8397) -> (29.4808, -8.9378)
  line L4 (29.4808, -8.9378) -> (22.4808, -21.0622)
extrude "Underside weight relief between actuator bays (6)" cut sketch "Underside weight relief between actuator bays (5)" along normal blind 3 bodies 1 in component "CORE | CoreTub"
ref_plane "WorkPlane1" through (0, 0, 0.5) normal (0, 0, 1) x (1, 0, 0) in component "CORE | CoreLid"
sketch "Low peripheral top skin" plane through (0, 0, 0.5) normal (0, 0, 1) x (1, 0, 0) in component "CORE | CoreLid"
  line L0 (71.1962, -3) -> (71.5433, -2.2961)
  line L1 (71.5433, -2.2961) -> (71.7956, -1.5529)
  line L2 (71.7956, -1.5529) -> (71.9487, -0.7832)
  line L3 (71.9487, -0.7832) -> (72, 0)
  line L4 (72, 0) -> (71.9487, 0.7832)
  line L5 (71.9487, 0.7832) -> (71.7956, 1.5529)
  line L6 (71.7956, 1.5529) -> (71.5433, 2.2961)
  line L7 (71.5433, 2.2961) -> (71.1962, 3)
  line L8 (71.1962, 3) -> (38.1962, 60.1577)
  line L9 (38.1962, 60.1577) -> (37.7601, 60.8102)
  line L10 (37.7601, 60.8102) -> (37.2426, 61.4003)
  line L11 (37.2426, 61.4003) -> (36.6526, 61.9178)
  line L12 (36.6526, 61.9178) -> (36, 62.3538)
  line L13 (36, 62.3538) -> (35.2961, 62.701)
  line L14 (35.2961, 62.701) -> (34.5529, 62.9532)
  line L15 (34.5529, 62.9532) -> (33.7832, 63.1063)
  line L16 (33.7832, 63.1063) -> (33, 63.1577)
  line L17 (33, 63.1577) -> (-33, 63.1577)
  line L18 (-33, 63.1577) -> (-33.7832, 63.1063)
  line L19 (-33.7832, 63.1063) -> (-34.5529, 62.9532)
  line L20 (-34.5529, 62.9532) -> (-35.2961, 62.701)
  line L21 (-35.2961, 62.701) -> (-36, 62.3538)
  line L22 (-36, 62.3538) -> (-36.6526, 61.9178)
  line L23 (-36.6526, 61.9178) -> (-37.2426, 61.4003)
  line L24 (-37.2426, 61.4003) -> (-37.7601, 60.8102)
  line L25 (-37.7601, 60.8102) -> (-38.1962, 60.1577)
  line L26 (-38.1962, 60.1577) -> (-71.1962, 3)
  line L27 (-71.1962, 3) -> (-71.5433, 2.2961)
  line L28 (-71.5433, 2.2961) -> (-71.7956, 1.5529)
  line L29 (-71.7956, 1.5529) -> (-71.9487, 0.7832)
  line L30 (-71.9487, 0.7832) -> (-72, 0)
  line L31 (-72, 0) -> (-71.9487, -0.7832)
  line L32 (-71.9487, -0.7832) -> (-71.7956, -1.5529)
  line L33 (-71.7956, -1.5529) -> (-71.5433, -2.2961)
  line L34 (-71.5433, -2.2961) -> (-71.1962, -3)
  line L35 (-71.1962, -3) -> (-38.1962, -60.1577)
  line L36 (-38.1962, -60.1577) -> (-37.7601, -60.8102)
  line L37 (-37.7601, -60.8102) -> (-37.2426, -61.4003)
  line L38 (-37.2426, -61.4003) -> (-36.6526, -61.9178)
  line L39 (-36.6526, -61.9178) -> (-36, -62.3538)
  line L40 (-36, -62.3538) -> (-35.2961, -62.701)
  line L41 (-35.2961, -62.701) -> (-34.5529, -62.9532)
  line L42 (-34.5529, -62.9532) -> (-33.7832, -63.1063)
  line L43 (-33.7832, -63.1063) -> (-33, -63.1577)
  line L44 (-33, -63.1577) -> (33, -63.1577)
  line L45 (33, -63.1577) -> (33.7832, -63.1063)
  line L46 (33.7832, -63.1063) -> (34.5529, -62.9532)
  line L47 (34.5529, -62.9532) -> (35.2961, -62.701)
  line L48 (35.2961, -62.701) -> (36, -62.3538)
  line L49 (36, -62.3538) -> (36.6526, -61.9178)
  line L50 (36.6526, -61.9178) -> (37.2426, -61.4003)
  line L51 (37.2426, -61.4003) -> (37.7601, -60.8102)
  line L52 (37.7601, -60.8102) -> (38.1962, -60.1577)
  line L53 (38.1962, -60.1577) -> (71.1962, -3)
extrude "Low peripheral top skin (1)" add sketch "Low peripheral top skin" along normal blind 2 separate body makes body 2 in component "CORE | CoreLid"
ref_plane "WorkPlane2" through (0, 0, 2.5) normal (0, 0, 1) x (1, 0, 0) in component "CORE | CoreLid"
sketch "Compact central enclosure island" plane through (0, 0, 2.5) normal (0, 0, 1) x (1, 0, 0) in component "CORE | CoreLid"
  circle A0 centre (0, 0) radius 31.6
extrude "Compact central enclosure island (1)" add sketch "Compact central enclosure island" along normal blind 7.9 bodies 2 in component "CORE | CoreLid"
ref_plane "WorkPlane3" through (0, 0, 10.4) normal (0, 0, 1) x (1, 0, 0) in component "CORE | CoreLid"
sketch "Soft crown edge section" plane through (0, 0, 10.4) normal (0, 0, 1) x (1, 0, 0) in component "CORE | CoreLid"
  circle A0 centre (0, 0) radius 31.6
ref_plane "WorkPlane4" through (0, 0, 12.4) normal (0, 0, 1) x (1, 0, 0) in component "CORE | CoreLid"
sketch "Soft crown edge section (1)" plane through (0, 0, 12.4) normal (0, 0, 1) x (1, 0, 0) in component "CORE | CoreLid"
  circle A0 centre (0, 0) radius 30.6
loft "Soft crown edge" add profiles "Soft crown edge section", "Soft crown edge section (1)" section 1 section 2 bodies 2 in component "CORE | CoreLid"
ref_plane "WorkPlane5" through (0, 0, 0.5) normal (0, 0, 1) x (1, 0, 0) in component "CORE | CoreLid"
sketch "Open underside cavity; 2.4mm roof" plane through (0, 0, 0.5) normal (0, 0, 1) x (1, 0, 0) in component "CORE | CoreLid"
  circle A0 centre (0, 0) radius 29.2
extrude "Open underside cavity; 2.4mm roof (1)" cut sketch "Open underside cavity; 2.4mm roof" along normal blind 9.5 bodies 2 in component "CORE | CoreLid"
ref_plane "WorkPlane6" through (0, 0, 0.5) normal (0, 0, 1) x (1, 0, 0) in component "CORE | CoreLid"
sketch "Yaw rotating hub peripheral clearance" plane through (0, 0, 0.5) normal (0, 0, 1) x (1, 0, 0) in component "CORE | CoreLid"
  circle A0 centre (49, 0) radius 16.8
extrude "Yaw rotating hub peripheral clearance (1)" cut sketch "Yaw rotating hub peripheral clearance" along normal blind 2 bodies 2 in component "CORE | CoreLid"
ref_plane "WorkPlane7" through (0, 0, 0.5) normal (0, 0, 1) x (1, 0, 0) in component "CORE | CoreLid"
sketch "Yaw rotating hub peripheral clearance (1)" plane through (0, 0, 0.5) normal (0, 0, 1) x (1, 0, 0) in component "CORE | CoreLid"
  circle A0 centre (24.5, 42.4352) radius 16.8
extrude "Yaw rotating hub peripheral clearance (2)" cut sketch "Yaw rotating hub peripheral clearance (1)" along normal blind 2 bodies 2 in component "CORE | CoreLid"
ref_plane "WorkPlane8" through (0, 0, 0.5) normal (0, 0, 1) x (1, 0, 0) in component "CORE | CoreLid"
sketch "Yaw rotating hub peripheral clearance (2)" plane through (0, 0, 0.5) normal (0, 0, 1) x (1, 0, 0) in component "CORE | CoreLid"
  circle A0 centre (-24.5, 42.4352) radius 16.8
extrude "Yaw rotating hub peripheral clearance (3)" cut sketch "Yaw rotating hub peripheral clearance (2)" along normal blind 2 bodies 2 in component "CORE | CoreLid"
ref_plane "WorkPlane9" through (0, 0, 0.5) normal (0, 0, 1) x (1, 0, 0) in component "CORE | CoreLid"
sketch "Yaw rotating hub peripheral clearance (3)" plane through (0, 0, 0.5) normal (0, 0, 1) x (1, 0, 0) in component "CORE | CoreLid"
  circle A0 centre (-49, 0) radius 16.8
extrude "Yaw rotating hub peripheral clearance (4)" cut sketch "Yaw rotating hub peripheral clearance (3)" along normal blind 2 bodies 2 in component "CORE | CoreLid"
ref_plane "WorkPlane10" through (0, 0, 0.5) normal (0, 0, 1) x (1, 0, 0) in component "CORE | CoreLid"
sketch "Yaw rotating hub peripheral clearance (4)" plane through (0, 0, 0.5) normal (0, 0, 1) x (1, 0, 0) in component "CORE | CoreLid"
  circle A0 centre (-24.5, -42.4352) radius 16.8
extrude "Yaw rotating hub peripheral clearance (5)" cut sketch "Yaw rotating hub peripheral clearance (4)" along normal blind 2 bodies 2 in component "CORE | CoreLid"
ref_plane "WorkPlane11" through (0, 0, 0.5) normal (0, 0, 1) x (1, 0, 0) in component "CORE | CoreLid"
sketch "Yaw rotating hub peripheral clearance (5)" plane through (0, 0, 0.5) normal (0, 0, 1) x (1, 0, 0) in component "CORE | CoreLid"
  circle A0 centre (24.5, -42.4352) radius 16.8
extrude "Yaw rotating hub peripheral clearance (6)" cut sketch "Yaw rotating hub peripheral clearance (5)" along normal blind 2 bodies 2 in component "CORE | CoreLid"
ref_plane "WorkPlane12" through (0, 0, -4) normal (0, 0, 1) x (1, 0, 0) in component "CORE | CoreLid"
sketch "Concealed integral lid insert boss" plane through (0, 0, -4) normal (0, 0, 1) x (1, 0, 0) in component "CORE | CoreLid"
  circle A0 centre (51.9615, 30) radius 5
extrude "Concealed integral lid insert boss (1)" add sketch "Concealed integral lid insert boss" along normal blind 4.5 bodies 2 in component "CORE | CoreLid"
ref_plane "WorkPlane13" through (0, 0, -4) normal (0, 0, 1) x (1, 0, 0) in component "CORE | CoreLid"
sketch "Blind provisional M3 insert cavity" plane through (0, 0, -4) normal (0, 0, 1) x (1, 0, 0) in component "CORE | CoreLid"
  circle A0 centre (51.9615, 30) radius 2.1
extrude "Blind provisional M3 insert cavity (1)" cut sketch "Blind provisional M3 insert cavity" along normal blind 4.3 bodies 2 in component "CORE | CoreLid"
ref_plane "WorkPlane14" through (0, 0, -4) normal (0, 0, 1) x (1, 0, 0) in component "CORE | CoreLid"
sketch "Concealed integral lid insert boss (1)" plane through (0, 0, -4) normal (0, 0, 1) x (1, 0, 0) in component "CORE | CoreLid"
  circle A0 centre (-51.9615, 30) radius 5
extrude "Concealed integral lid insert boss (2)" add sketch "Concealed integral lid insert boss (1)" along normal blind 4.5 bodies 2 in component "CORE | CoreLid"
ref_plane "WorkPlane15" through (0, 0, -4) normal (0, 0, 1) x (1, 0, 0) in component "CORE | CoreLid"
sketch "Blind provisional M3 insert cavity (1)" plane through (0, 0, -4) normal (0, 0, 1) x (1, 0, 0) in component "CORE | CoreLid"
  circle A0 centre (-51.9615, 30) radius 2.1
extrude "Blind provisional M3 insert cavity (2)" cut sketch "Blind provisional M3 insert cavity (1)" along normal blind 4.3 bodies 2 in component "CORE | CoreLid"
ref_plane "WorkPlane16" through (0, 0, -4) normal (0, 0, 1) x (1, 0, 0) in component "CORE | CoreLid"
sketch "Concealed integral lid insert boss (2)" plane through (0, 0, -4) normal (0, 0, 1) x (1, 0, 0) in component "CORE | CoreLid"
  circle A0 centre (-51.9615, -30) radius 5
extrude "Concealed integral lid insert boss (3)" add sketch "Concealed integral lid insert boss (2)" along normal blind 4.5 bodies 2 in component "CORE | CoreLid"
ref_plane "WorkPlane17" through (0, 0, -4) normal (0, 0, 1) x (1, 0, 0) in component "CORE | CoreLid"
sketch "Blind provisional M3 insert cavity (2)" plane through (0, 0, -4) normal (0, 0, 1) x (1, 0, 0) in component "CORE | CoreLid"
  circle A0 centre (-51.9615, -30) radius 2.1
extrude "Blind provisional M3 insert cavity (3)" cut sketch "Blind provisional M3 insert cavity (2)" along normal blind 4.3 bodies 2 in component "CORE | CoreLid"
ref_plane "WorkPlane18" through (0, 0, -4) normal (0, 0, 1) x (1, 0, 0) in component "CORE | CoreLid"
sketch "Concealed integral lid insert boss (3)" plane through (0, 0, -4) normal (0, 0, 1) x (1, 0, 0) in component "CORE | CoreLid"
  circle A0 centre (51.9615, -30) radius 5
extrude "Concealed integral lid insert boss (4)" add sketch "Concealed integral lid insert boss (3)" along normal blind 4.5 bodies 2 in component "CORE | CoreLid"
ref_plane "WorkPlane19" through (0, 0, -4) normal (0, 0, 1) x (1, 0, 0) in component "CORE | CoreLid"
sketch "Blind provisional M3 insert cavity (3)" plane through (0, 0, -4) normal (0, 0, 1) x (1, 0, 0) in component "CORE | CoreLid"
  circle A0 centre (51.9615, -30) radius 2.1
extrude "Blind provisional M3 insert cavity (4)" cut sketch "Blind provisional M3 insert cavity (3)" along normal blind 4.3 bodies 2 in component "CORE | CoreLid"
ref_plane "WorkPlane1" through (0, 0, -15) normal (0, 0, 1) x (1, 0, 0) in component "CORE | ElectronicsCassette"
sketch "Low removable electronics carrier" plane through (0, 0, -15) normal (0, 0, 1) x (1, 0, 0) in component "CORE | ElectronicsCassette"
  circle A0 centre (0, 0) radius 28.8
extrude "Low removable electronics carrier (1)" add sketch "Low removable electronics carrier" along normal blind 2 separate body makes body 3 in component "CORE | ElectronicsCassette"
ref_plane "WorkPlane2" through (0, 0, -15) normal (0, 0, 1) x (1, 0, 0) in component "CORE | ElectronicsCassette"
sketch "Yaw bay clearance with 0.4mm allowance" plane through (0, 0, -15) normal (0, 0, 1) x (1, 0, 0) in component "CORE | ElectronicsCassette"
  line L0 (26.6, -6.9) -> (59.4, -6.9)
  line L1 (59.4, -6.9) -> (59.4, 6.9)
  line L2 (59.4, 6.9) -> (26.6, 6.9)
  line L3 (26.6, 6.9) -> (26.6, -6.9)
extrude "Yaw bay clearance with 0.4mm allowance (1)" cut sketch "Yaw bay clearance with 0.4mm allowance" along normal blind 2 bodies 3 in component "CORE | ElectronicsCassette"
ref_plane "WorkPlane3" through (0, 0, -15) normal (0, 0, 1) x (1, 0, 0) in component "CORE | ElectronicsCassette"
sketch "Yaw bay clearance with 0.4mm allowance (1)" plane through (0, 0, -15) normal (0, 0, 1) x (1, 0, 0) in component "CORE | ElectronicsCassette"
  line L0 (19.2756, 19.5863) -> (35.6756, 47.9919)
  line L1 (35.6756, 47.9919) -> (23.7244, 54.8919)
  line L2 (23.7244, 54.8919) -> (7.3244, 26.4863)
  line L3 (7.3244, 26.4863) -> (19.2756, 19.5863)
extrude "Yaw bay clearance with 0.4mm allowance (2)" cut sketch "Yaw bay clearance with 0.4mm allowance (1)" along normal blind 2 bodies 3 in component "CORE | ElectronicsCassette"
ref_plane "WorkPlane4" through (0, 0, -15) normal (0, 0, 1) x (1, 0, 0) in component "CORE | ElectronicsCassette"
sketch "Yaw bay clearance with 0.4mm allowance (2)" plane through (0, 0, -15) normal (0, 0, 1) x (1, 0, 0) in component "CORE | ElectronicsCassette"
  line L0 (-7.3244, 26.4863) -> (-23.7244, 54.8919)
  line L1 (-23.7244, 54.8919) -> (-35.6756, 47.9919)
  line L2 (-35.6756, 47.9919) -> (-19.2756, 19.5863)
  line L3 (-19.2756, 19.5863) -> (-7.3244, 26.4863)
extrude "Yaw bay clearance with 0.4mm allowance (3)" cut sketch "Yaw bay clearance with 0.4mm allowance (2)" along normal blind 2 bodies 3 in component "CORE | ElectronicsCassette"
ref_plane "WorkPlane5" through (0, 0, -15) normal (0, 0, 1) x (1, 0, 0) in component "CORE | ElectronicsCassette"
sketch "Yaw bay clearance with 0.4mm allowance (3)" plane through (0, 0, -15) normal (0, 0, 1) x (1, 0, 0) in component "CORE | ElectronicsCassette"
  line L0 (-26.6, 6.9) -> (-59.4, 6.9)
  line L1 (-59.4, 6.9) -> (-59.4, -6.9)
  line L2 (-59.4, -6.9) -> (-26.6, -6.9)
  line L3 (-26.6, -6.9) -> (-26.6, 6.9)
extrude "Yaw bay clearance with 0.4mm allowance (4)" cut sketch "Yaw bay clearance with 0.4mm allowance (3)" along normal blind 2 bodies 3 in component "CORE | ElectronicsCassette"
ref_plane "WorkPlane6" through (0, 0, -15) normal (0, 0, 1) x (1, 0, 0) in component "CORE | ElectronicsCassette"
sketch "Yaw bay clearance with 0.4mm allowance (4)" plane through (0, 0, -15) normal (0, 0, 1) x (1, 0, 0) in component "CORE | ElectronicsCassette"
  line L0 (-19.2756, -19.5863) -> (-35.6756, -47.9919)
  line L1 (-35.6756, -47.9919) -> (-23.7244, -54.8919)
  line L2 (-23.7244, -54.8919) -> (-7.3244, -26.4863)
  line L3 (-7.3244, -26.4863) -> (-19.2756, -19.5863)
extrude "Yaw bay clearance with 0.4mm allowance (5)" cut sketch "Yaw bay clearance with 0.4mm allowance (4)" along normal blind 2 bodies 3 in component "CORE | ElectronicsCassette"
ref_plane "WorkPlane7" through (0, 0, -15) normal (0, 0, 1) x (1, 0, 0) in component "CORE | ElectronicsCassette"
sketch "Yaw bay clearance with 0.4mm allowance (5)" plane through (0, 0, -15) normal (0, 0, 1) x (1, 0, 0) in component "CORE | ElectronicsCassette"
  line L0 (7.3244, -26.4863) -> (23.7244, -54.8919)
  line L1 (23.7244, -54.8919) -> (35.6756, -47.9919)
  line L2 (35.6756, -47.9919) -> (19.2756, -19.5863)
  line L3 (19.2756, -19.5863) -> (7.3244, -26.4863)
extrude "Yaw bay clearance with 0.4mm allowance (6)" cut sketch "Yaw bay clearance with 0.4mm allowance (5)" along normal blind 2 bodies 3 in component "CORE | ElectronicsCassette"
ref_plane "WorkPlane8" through (0, 0, -15) normal (0, 0, 1) x (1, 0, 0) in component "CORE | ElectronicsCassette"
sketch "Two hidden carrier fastener paths" plane through (0, 0, -15) normal (0, 0, 1) x (1, 0, 0) in component "CORE | ElectronicsCassette"
  circle A0 centre (21, 16) radius 1.7
extrude "Two hidden carrier fastener paths (1)" cut sketch "Two hidden carrier fastener paths" along normal blind 2 bodies 3 in component "CORE | ElectronicsCassette"
ref_plane "WorkPlane9" through (0, 0, -15) normal (0, 0, 1) x (1, 0, 0) in component "CORE | ElectronicsCassette"
sketch "Two hidden carrier fastener paths (1)" plane through (0, 0, -15) normal (0, 0, 1) x (1, 0, 0) in component "CORE | ElectronicsCassette"
  circle A0 centre (-21, -16) radius 1.7
extrude "Two hidden carrier fastener paths (2)" cut sketch "Two hidden carrier fastener paths (1)" along normal blind 2 bodies 3 in component "CORE | ElectronicsCassette"
ref_plane "WorkPlane10" through (0, 0, -13) normal (0, 0, 1) x (1, 0, 0) in component "CORE | ElectronicsCassette"
sketch "Rotated regulator insulating support" plane through (0, 0, -13) normal (0, 0, 1) x (1, 0, 0) in component "CORE | ElectronicsCassette"
  circle A0 centre (-2.9904, -24.8205) radius 2
extrude "Rotated regulator insulating support (1)" add sketch "Rotated regulator insulating support" along normal blind 1 bodies 3 in component "CORE | ElectronicsCassette"
ref_plane "WorkPlane11" through (0, 0, -13) normal (0, 0, 1) x (1, 0, 0) in component "CORE | ElectronicsCassette"
sketch "Rotated regulator insulating support (1)" plane through (0, 0, -13) normal (0, 0, 1) x (1, 0, 0) in component "CORE | ElectronicsCassette"
  circle A0 centre (-22.9904, 9.8205) radius 2
extrude "Rotated regulator insulating support (2)" add sketch "Rotated regulator insulating support (1)" along normal blind 1 bodies 3 in component "CORE | ElectronicsCassette"
ref_plane "WorkPlane12" through (0, 0, -13) normal (0, 0, 1) x (1, 0, 0) in component "CORE | ElectronicsCassette"
sketch "Rotated regulator insulating support (2)" plane through (0, 0, -13) normal (0, 0, 1) x (1, 0, 0) in component "CORE | ElectronicsCassette"
  circle A0 centre (22.9904, -9.8205) radius 2
extrude "Rotated regulator insulating support (3)" add sketch "Rotated regulator insulating support (2)" along normal blind 1 bodies 3 in component "CORE | ElectronicsCassette"
ref_plane "WorkPlane13" through (0, 0, -13) normal (0, 0, 1) x (1, 0, 0) in component "CORE | ElectronicsCassette"
sketch "Rotated regulator insulating support (3)" plane through (0, 0, -13) normal (0, 0, 1) x (1, 0, 0) in component "CORE | ElectronicsCassette"
  circle A0 centre (2.9904, 24.8205) radius 2
extrude "Rotated regulator insulating support (4)" add sketch "Rotated regulator insulating support (3)" along normal blind 1 bodies 3 in component "CORE | ElectronicsCassette"
ref_plane "WorkPlane14" through (0, 0, -13) normal (0, 0, 1) x (1, 0, 0) in component "CORE | ElectronicsCassette"
sketch "Controller support outside regulator reserve" plane through (0, 0, -13) normal (0, 0, 1) x (1, 0, 0) in component "CORE | ElectronicsCassette"
  line L0 (-25.8, -4.8) -> (-24.2, -4.8)
  line L1 (-24.2, -4.8) -> (-24.2, -3.2)
  line L2 (-24.2, -3.2) -> (-25.8, -3.2)
  line L3 (-25.8, -3.2) -> (-25.8, -4.8)
extrude "Controller support outside regulator reserve (1)" add sketch "Controller support outside regulator reserve" along normal blind 13 bodies 3 in component "CORE | ElectronicsCassette"
ref_plane "WorkPlane15" through (0, 0, -13) normal (0, 0, 1) x (1, 0, 0) in component "CORE | ElectronicsCassette"
sketch "Controller support outside regulator reserve (1)" plane through (0, 0, -13) normal (0, 0, 1) x (1, 0, 0) in component "CORE | ElectronicsCassette"
  line L0 (-25.8, 3.2) -> (-24.2, 3.2)
  line L1 (-24.2, 3.2) -> (-24.2, 4.8)
  line L2 (-24.2, 4.8) -> (-25.8, 4.8)
  line L3 (-25.8, 4.8) -> (-25.8, 3.2)
extrude "Controller support outside regulator reserve (2)" add sketch "Controller support outside regulator reserve (1)" along normal blind 13 bodies 3 in component "CORE | ElectronicsCassette"
ref_plane "WorkPlane16" through (0, 0, -13) normal (0, 0, 1) x (1, 0, 0) in component "CORE | ElectronicsCassette"